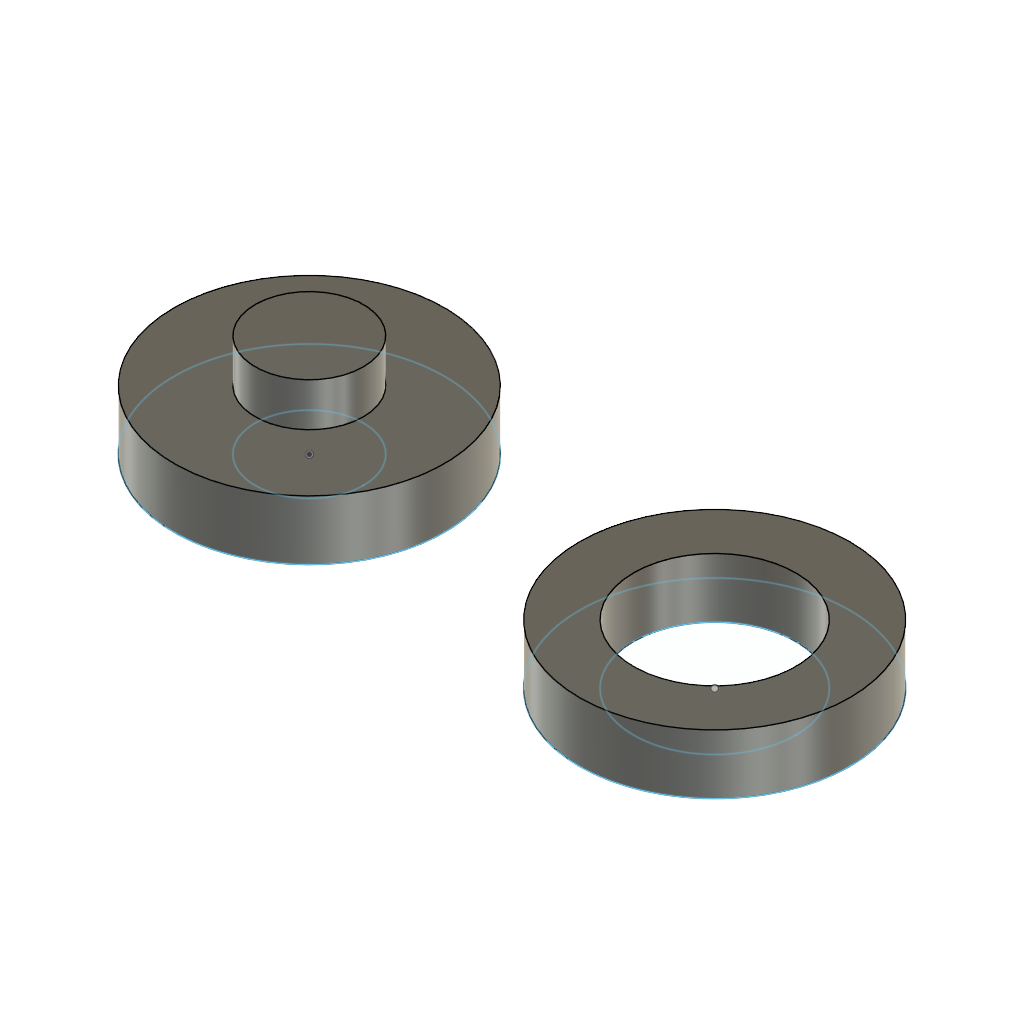
spacers (Autodesk Fusion 360 design; units mm, degrees)
Autodesk Fusion 360 part; units mm, degrees
sketch "Sketch1" plane through (0, 0, 0) normal (0, 0, 1) x (1, 0, 0)
  circle A0 centre (0, 0) radius 2.5
  circle A1 centre (0, 0) radius 1
  circle A2 centre (7.5, 0) radius 2.5
  circle A3 centre (7.5, 0) radius 1.5
  constraint coincident A0.centre A1.centre
  constraint concentric A2 A3
extrude "Extrude1" add sketch "Sketch1" along normal blind 1.9 contours A1 makes body 1
extrude "Extrude2" add sketch "Sketch1" along normal blind 1.1 contours A0 bodies 1
extrude "Extrude3" add sketch "Sketch1" along normal blind 1.1 separate body contours A2 makes body 2
